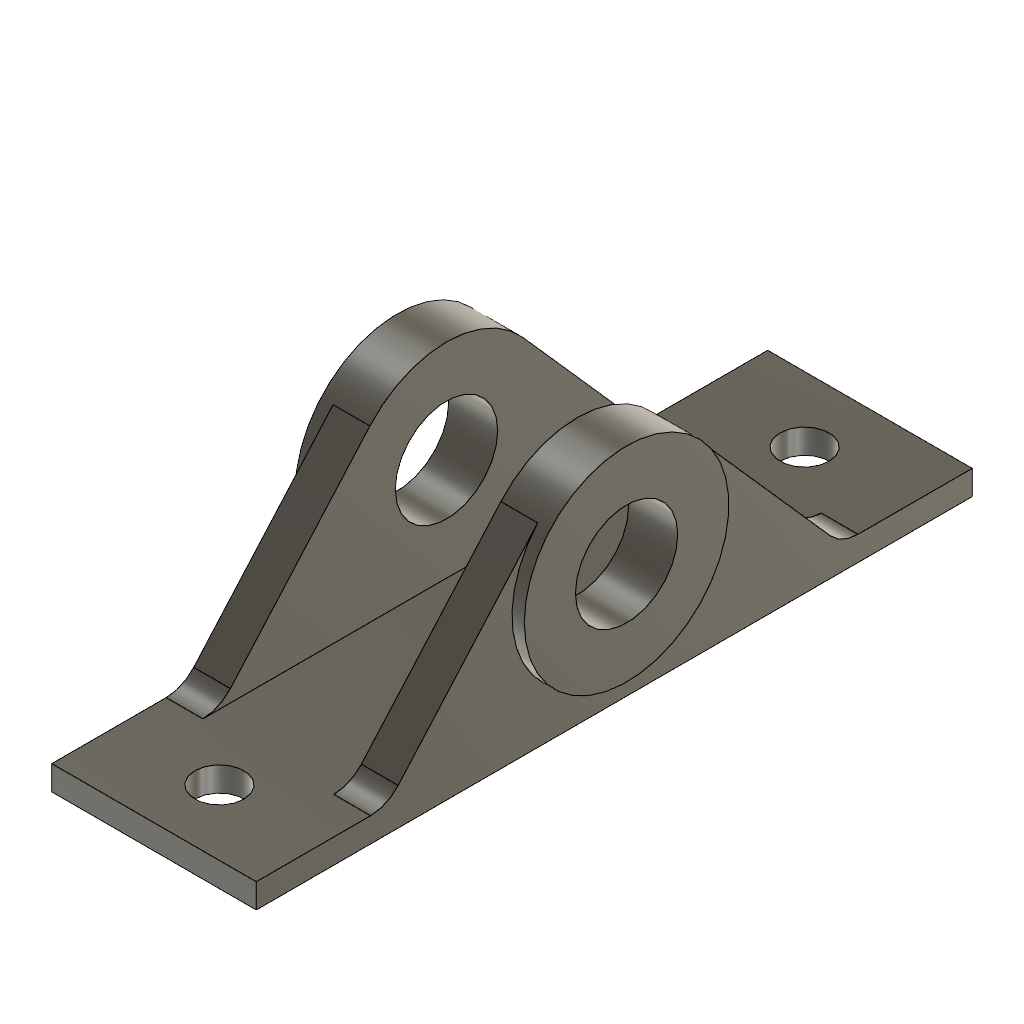
Shape 1 (Autodesk Fusion 360 design; units mm, degrees)
part number: 2026-11-07-23-48-18-165
Autodesk Fusion 360 part; units mm, degrees
sketch "Sketch4" plane through (0, 0, 0) normal (0, 0, 1) x (1, 0, 0)
  line L0 (25, -87.5) -> (-25, -87.5)
  line L1 (-25, -87.5) -> (-25, 87.5)
  line L2 (-25, 87.5) -> (25, 87.5)
  line L3 (25, 87.5) -> (25, -87.5)
  line L4 (25, -87.5) -> (-25, 87.5) construction
  line L5 (-25, -87.5) -> (25, 87.5) construction
  dimension "d6" = 50
  dimension "d7" = 175
  constraint horizontal L0
  constraint perpendicular L0 L1
  constraint parallel L0 L2
  constraint parallel L1 L3
  constraint coincident L4 origin
  constraint coincident L5 origin
  measures "d6" distance of L1.end L2.end
  measures "d7" distance of L0.end L1.end
extrude "Extrude2" add sketch "Sketch4" along normal blind 6
sketch "Sketch5" plane through (0, 0, 6) normal (0, 0, 1) x (-1, 0, 0)
  line L0 (-25, -87.5) -> (25, -87.5)
  line L1 (25, -87.5) -> (25, 87.5)
  line L2 (25, 87.5) -> (-25, 87.5)
  line L3 (-25, 87.5) -> (-25, -87.5)
  line L4 (0, 104.831) -> (0, -112.2011) construction
  circle A0 centre (0, 71.5) radius 6
  line L5 (50.14, 0) -> (-56.4087, 0) construction
  circle A1 centre (0, -71.5) radius 6
  dimension "d10" = 12
  dimension "d11" = 16
  dimension "d12" = 25
  constraint perpendicular L2 L4
  constraint coincident L4 A0.centre
  constraint perpendicular L1 L5
  constraint symmetric A0 L5 A1
  measures "d10" diameter of A0
  measures "d11" distance of L2 A0.centre
  measures "d12" distance of L3 A0.centre
extrude "Extrude3" cut sketch "Sketch5" against normal up to surface (6 mm away) contours A0 | A1
sketch "Sketch6" plane through (0, 0, 6) normal (0, 0, 1) x (-1, 0, 0)
  circle A0 centre (0, 71.5) radius 6
  circle A1 centre (0, -71.5) radius 6
  line L0 (-25, -87.5) -> (25, -87.5)
  line L1 (25, -87.5) -> (25, 87.5)
  line L2 (25, 87.5) -> (-25, 87.5)
  line L3 (-25, 87.5) -> (-25, -87.5)
sketch "Sketch7" plane through (25, 0, 0) normal (1, 0, 0) x (0, 1, 0)
  line L0 (-87.5, 0) -> (87.5, 0)
  line L1 (87.5, 0) -> (87.5, 6)
  line L2 (87.5, 6) -> (-87.5, 6)
  line L3 (-87.5, 6) -> (-87.5, 0)
  line L4 (0, -24.3483) -> (0, 83.4114) construction
  circle A0 centre (0, 31) radius 25
  line L5 (-55.5, 6) -> (-18.7234, 47.566)
  line L6 (55.5, 6) -> (18.7234, 47.566)
  circle A1 centre (0, 31) radius 12.5
  dimension "d15" = 50
  dimension "d16" = 31
  dimension "d17" = 32
  dimension "d26" = 25
  constraint perpendicular L0 L4
  constraint coincident L4 A0.centre
  constraint coincident L2 L5.start
  constraint coincident A0 L5.end
  constraint tangent A0 L5
  constraint symmetric L4 L5.start L6.start
  constraint symmetric L4 L5.end L6.end
  constraint concentric A0 A1
  measures "d15" diameter of A0
  measures "d16" distance of origin A0.centre
  measures "d17" distance of L3 L5.start
  measures "d26" diameter of A1
extrude "Extrude4" add sketch "Sketch7" against normal blind 9 contours L2 A0 L5 | L2 A0 L6
extrude "Extrude5" add sketch "Sketch7" along normal blind 3 and the other way blind 9 contours A0
fillet "Fillet1" radius 9 2 edges at (20.5, -55.5, 6) (20.5, 55.5, 6)
mirror "Mirror1" about plane through (0, 0, 0) normal (1, 0, 0) of bodies 1 merged
equation "d16 = 25 mm + 6 mm"
